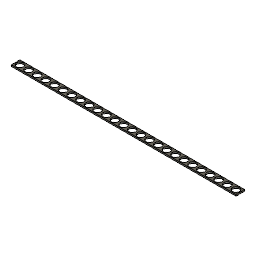
endplate_26fori (Autodesk Fusion 360 design; units mm, degrees)
part number: 2026-07-22-14-33-01-553
Autodesk Fusion 360 part; units mm, degrees
sketch "Sketch1" plane through (0, 0, 0) normal (0, 0, 1) x (1, 0, 0)
  line L0 (0, 0) -> (619, 0)
  line L1 (619, 0) -> (619, 24)
  line L2 (619, 24) -> (0, 24)
  line L3 (0, 24) -> (0, 0)
extrude "Extrude1" add sketch "Sketch1" along normal blind 4
sketch "Sketch2" plane through (0, 0, 0) normal (0, 0, 1) x (1, 0, 0)
  circle A0 centre (12, 12) radius 9.5
extrude "Extrude2" cut sketch "Sketch2" along normal blind 4
pattern_linear "R-Pattern1" count 26 spacing 23.8 along (1, 0, 0) count 3 spacing 0 along (1, 0, 0) of "Extrude2"
named bodies: "end_plate_4mm"
